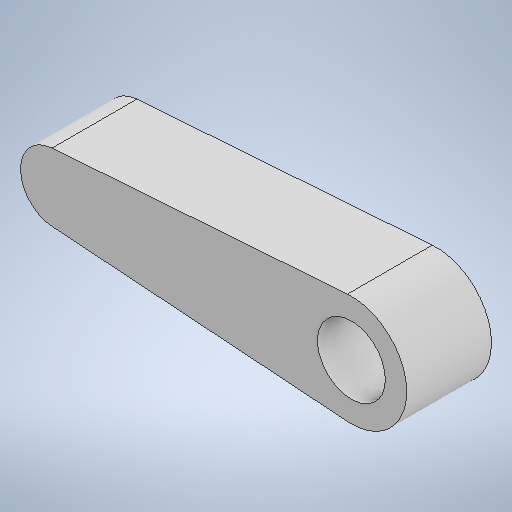
# Autodesk Inventor part: seguidor2
Saved by Autodesk Inventor 2025.2 (Build 292293000, 293)
## iProperties
Created: 2025-05-16
Part Number: seguidor2
Material: Generic
Document SubType Name: Modeling
Designer: laura
Density: 1 g/cm^3
Appearance: Default
Author: laura
Autodesk Inventor part; units mm, degrees
ref_plane "YZ Plane" through (0, 0, 0) normal (1, 0, 0) x (0, 1, 0)
ref_plane "XZ Plane" through (0, 0, 0) normal (0, 1, 0) x (-1, 0, 0)
ref_plane "XY Plane" through (0, 0, 0) normal (0, 0, 1) x (1, 0, 0)
sketch "Sketch1" plane through (0, 0, 0) normal (0, 0, 1) x (1, 0, 0)
  circle A0 centre (0, 0) radius 4
  line L0 (-0.4667, -6.5) -> (-35.2872, -4)
  arc A1 (-35.2872, 4) -> (-35.2872, -4) centre (-35, 0) ccw
  line L1 (-35.2872, 4) -> (-0.4667, 6.5)
  arc A2 (-0.4667, -6.5) -> (-0.4667, 6.5) centre (0, 0) ccw
  line L2 (0, 0) -> (-35, 0) construction
  dimension "d2" = 8
  dimension "d4" = 13
  dimension "d5" = 8
  dimension "d6" = 35
  constraints: 6 end point, 4 point on circle, 4 tangent, 3 centre point, 3 coincident, 1 horizontal
  measures "d2" diameter of A0
  measures "d4" distance of L1.end L0.start
  measures "d5" distance of L1.start L0.end
  measures "d6" distance of L2.start L2.end
extrude "Extrusion1" add sketch "Sketch1" along normal blind 10
sketch "Sketch2" plane through (-0.4667, -6.5, 0) normal (-0.0716, -0.9974, 0) x (0.9974, -0.0716, 0)
  circle A0 centre (-31.9101, 5) radius 1.5
  line L0 (-34.9101, 10) -> (0, 10) projected
  line L1 (-31.9101, 10) -> (-31.9101, 0) construction
  line L2 (-34.9101, 0) -> (0, 0) projected
  line L3 (-34.9101, 0) -> (-34.9101, 10) projected
  line L4 (-31.9101, 5) -> (-34.9101, 5) construction
  dimension "d10" = 3
  dimension "d11" = 3
  constraints: 4 end point, 2 midpoint, 2 point on line, 1 centre point, 1 coincident, 1 vertical
  measures "d10" distance between parallel lines of L3 L1
  measures "d11" diameter of A0
extrude "Extrusion2" cut sketch "Sketch2" against normal blind 1
body "Solid1"
